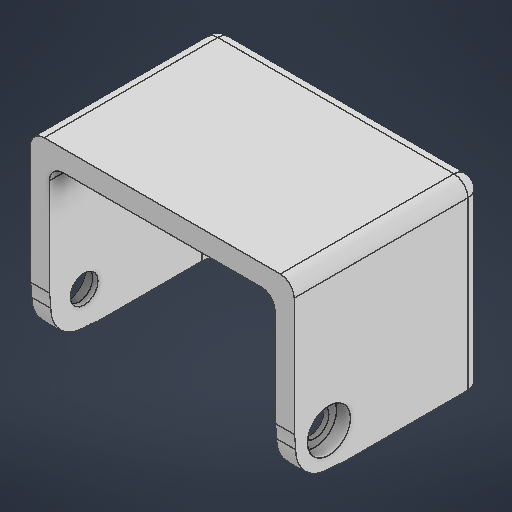
# Autodesk Inventor part: 5521DC Power Box_b
Saved by Autodesk Inventor 2026.2 (Build 302298010, 298A)
## iProperties
Created: 2026-05-09
Part Number: 5521DC Power Box_b
Material: 일반
Document SubType Name: Modeling
Designer: work
Density: 1 g/cm^3
Appearance: 기본값
Author: work
Autodesk Inventor part; units mm, degrees
ref_plane "YZ Plane" through (0, 0, 0) normal (1, 0, 0) x (0, 1, 0)
ref_plane "XZ Plane" through (0, 0, 0) normal (0, 1, 0) x (-1, 0, 0)
ref_plane "XY Plane" through (0, 0, 0) normal (0, 0, 1) x (1, 0, 0)
sketch "스케치1" plane through (0, 0, 0) normal (1, 0, 0) x (0, 1, 0)
  line L0 (0, 0) -> (23, 0)
  line L1 (23, 0) -> (23, -24)
  line L2 (23, -24) -> (0, -24)
  line L3 (0, -24) -> (0, 0)
  line L4 (0, 0) -> (26, 0)
  line L5 (26, 0) -> (26, -27)
  line L6 (26, -27) -> (0, -27)
  line L7 (0, -27) -> (0, 0)
  point P0 (26, -13.5)
  dimension "d0" = 23
  dimension "d1" = 24
  dimension "d2" = 3
  dimension "d3" = 3
  constraints: 16 end point, 4 parallel, 2 horizontal, 2 perpendicular, 1 midpoint
  measures "d0" distance of L1.end L2.end
  measures "d1" distance of L0.end L1.end
  measures "d2" distance from line of point (26, -13.5) L1
  measures "d3" distance between parallel lines of L6 L2
extrude "돌출1" add sketch "스케치1" along normal mid plane 38
extrude "돌출2" cut sketch "스케치1" along normal mid plane 32.5 contours L0 L1 L2 L3
sketch "스케치2" plane through (19, 26, -27) normal (0, 0, -1) x (-1, 0, 0)
  line L0 (19, -26) -> (19, -18) construction
  line L1 (21.5, -26) -> (21.5, -18)
  line L2 (16.5, -18) -> (16.5, -26)
  arc A0 (16.5, -26) -> (21.5, -26) centre (19, -26) ccw
  arc A1 (21.5, -18) -> (16.5, -18) centre (19, -18) ccw
  point P0 (19, -22)
  dimension "d8" = 2.5
  dimension "d9" = 8
  constraints: 8 end point, 4 point on circle, 4 tangent, 2 centre point, 1 midpoint, 1 parallel, 1 vertical
  measures "d8" radius of A1
  measures "d9" distance of L0.start L0.end
extrude "돌출3" cut sketch "스케치2" against normal blind 31.5
fillet "모깎기1" radius 2 10 edges at (-16.25, 11.5, -24) (-16.25, 23, -12) (0, 23, -24) (16.25, 11.5, -24) (16.25, 23, -12) (-19, 26, -13.5) (-19, 13, -27) (0, 26, -27) (19, 26, -13.5) (19, 13, -27)
sketch "스케치3" plane through (19, 0, 0) normal (1, 0, 0) x (0, 0, -1)
  circle A0 centre (5, 5) radius 2
  point P0 (0, 0)
  dimension "d13" = 4
  dimension "d14" = 5
  dimension "d15" = 5
  constraints: 1 centre point
  measures "d13" diameter of A0
  measures "d14" horizontal distance of point (0, 0) A0.centre
  measures "d15" horizontal distance of point (0, 0) A0.centre
extrude "돌출4" cut sketch "스케치3" against normal through all
sketch "스케치4" plane through (19, 0, 0) normal (1, 0, 0) x (0, 0, -1)
  circle A0 centre (5, 5) radius 2 projected
  point P0 (0, 0)
  constraints: 1 coincident
hole "구멍1" at (19, 5, -5) direction (-1, 0, 0) diameter 4 end through all counterbore diameter 6.2 counterbore depth 2
sketch "스케치5" plane through (-19, 0, 0) normal (-1, 0, 0) x (0, 0, 1)
  circle A0 centre (-5, 5) radius 2 projected
  point P0 (0, 0)
  constraints: 1 coincident
hole "구멍2" at (-19, 5, -5) direction (1, 0, 0) diameter 4 end through all counterbore diameter 6.2 counterbore depth 2
sketch "스케치6" plane through (19, 0, 0) normal (1, 0, 0) x (0, 0, -1)
  circle A0 centre (5, 5) radius 3.1 projected
  line L0 (25, 24) -> (25, 0) projected
  line L1 (0, 24) -> (25, 24) projected
  line L2 (0, 24) -> (0, 0) projected
  line L3 (0, 0) -> (25, 0) projected
  circle A1 centre (5, 5) radius 5
  circle A2 centre (5, 5) radius 4.8
  arc A3 (7.0048, 0) -> (5.0048, 0.2) centre (5.0148, -9.8) ccw
  arc A4 (0.2, 5.0048) -> (0, 7.0048) centre (-9.8, 5.0148) ccw
  dimension "d32" = 0.2
  dimension "d33" = 10
  dimension "d34" = 2
  dimension "d35" = 2
  dimension "d36" = 10
  constraints: 6 point on circle, 4 centre point, 3 tangent, 2 coincident, 2 point on line
  measures "d32" radial gap between concentric circles of A1 A2
  measures "d33" radius of A3
  measures "d34" horizontal distance of A2.start A3.start
  measures "d35" vertical distance of A2.end A4.end
  measures "d36" radius of A4
extrude "돌출5" cut sketch "스케치6" against normal through all contours L3 A1 A3 | A4 A1 L2 | L3 L2 A1 | A1 A4 A2 A3 picked at (1.4067, 1.6604)
fillet "모깎기2" radius 2 2 edges at (-2.5, 0, -25.5) (2.5, 0, -25.5)
